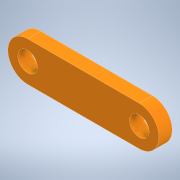
# Autodesk Inventor part: 24-10-25-linkLawrence-A2213271-v1
Saved by Autodesk Inventor 2022 (Build 260153000, 153)
## iProperties
Created: 2024-10-25
Part Number: 24-10-25-linkLawrence-A2213271-v1
Material: Generic
Document SubType Name: Modeling
Designer: Dell
Density: 1 g/cm^3
Appearance: Orange
Author: Dell
Autodesk Inventor part; units mm, degrees
ref_plane "YZ Plane" through (0, 0, 0) normal (1, 0, 0) x (0, 1, 0)
ref_plane "XZ Plane" through (0, 0, 0) normal (0, 1, 0) x (-1, 0, 0)
ref_plane "XY Plane" through (0, 0, 0) normal (0, 0, 1) x (1, 0, 0)
sketch "Sketch1" plane through (0, 0, 0) normal (0, 0, 1) x (1, 0, 0)
  line L0 (0, 0) -> (-85, 0) construction
  line L1 (0, 15) -> (-85, 15)
  line L2 (-85, -15) -> (0, -15)
  arc A0 (0, -15) -> (0, 15) centre (0, 0) ccw
  arc A1 (-85, 15) -> (-85, -15) centre (-85, 0) ccw
  circle A2 centre (-85, 0) radius 7.5
  circle A3 centre (0, 0) radius 7.5
  point P0 (-42.5, 0)
  dimension "d0" = 85
  dimension "d1" = 30
  dimension "d2" = 15
  dimension "d3" = 15
  constraints: 8 end point, 4 centre point, 4 point on circle, 4 tangent, 2 coincident, 1 horizontal, 1 midpoint, 1 parallel
  measures "d0" distance of L0.start L0.end
  measures "d1" diameter of A1
  measures "d2" diameter of A2
  measures "d3" diameter of A3
extrude "Extrusion1" add sketch "Sketch1" along normal blind 10
body "Solid1"
